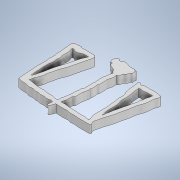
# Autodesk Inventor part: balanta
Saved by Autodesk Inventor 2022.6 (Build 266554000, 554)
## iProperties
Created: 2024-11-29
Part Number: balanta
Material: Generic
Document SubType Name: Modeling
Designer: Dragos Macovei
Density: 1 g/cm^3
Appearance: Default
Author: Dragos Macovei
Autodesk Inventor part; units mm, degrees
ref_plane "YZ Plane" through (0, 0, 0) normal (1, 0, 0) x (0, 1, 0)
ref_plane "XZ Plane" through (0, 0, 0) normal (0, 1, 0) x (-1, 0, 0)
ref_plane "XY Plane" through (0, 0, 0) normal (0, 0, 1) x (1, 0, 0)
sketch "Sketch1" plane through (0, 0, 0) normal (0, 1, 0) x (-1, 0, 0)
  line L0 (0, 0) -> (40, 0)
  line L1 (40, 0) -> (40, 40)
  line L2 (40, 40) -> (0, 40)
  line L3 (0, 40) -> (0, 0)
  line L4 (-121.6723, 119.328) -> (149.4788, 116.0761) construction
  line L5 (149.4788, 116.0761) -> (145.1429, -245.4588) construction
  line L6 (145.1429, -245.4588) -> (-126.0082, -242.2068) construction
  line L7 (-126.0082, -242.2068) -> (-121.6723, 119.328) construction
  spline S0 degree 4 poles (18.132, 10.989) (16.9377, 10.9556) (17.9969, 8.7031) (16.3174, 9.7065) (16.3802, 7.1587) (15.244, 7.8186) (16.3931, 5.6588) (15.388, 6.4386) (15.9001, 5.8958) knots 0 0 0 0 0 0.382596 0.513783 0.647859 0.765558 1 1 1 1 1
  spline S1 degree 4 poles (15.9001, 5.8958) (16.1869, 6.4535) (16.7122, 5.1482) (16.9845, 5.99) (17.8067, 5.5515) (18.1772, 5.8918) (19.1534, 5.4252) (20.1172, 5.2229) (21.245, 4.874) (21.9533, 5.6519) (22.2326, 5.7647) (22.3392, 5.669) knots 0 0 0 0 0 0.217748 0.302019 0.392709 0.499027 0.616777 0.744599 0.858933 1 1 1 1 1
  arc A0 (23.208, 5.1808) -> (23.5743, 7.797) centre (22.364, 6.6327) ccw
  spline S2 degree 4 poles (19.493, 10.8143) (20.5057, 10.7236) (19.2906, 9.4163) (23.7596, 9.3762) (22.5943, 7.6044) (23.2286, 7.7842) (23.5743, 7.797) knots 0 0 0 0 0 0.530729 0.735737 1 1 1 1 1
  line L8 (22.8288, 7.7694) -> (24.3198, 7.8246) construction
  arc A1 (24.1442, 7.7271) -> (23.0111, 7.6852) centre (23.6414, 5.984) ccw construction
  arc A2 (22.3392, 5.669) -> (23.208, 5.1808) centre (23.0369, 5.8934) ccw
  spline S3 degree 2 poles (23.208, 5.1808) (23.1636, 5.1563) (23.1223, 5.1342) knots 0 0 0 1 1 1
  spline S4 degree 2 poles (22.5517, 4.9638) (22.5482, 4.9867) (22.5627, 5.0238) knots 0 0 0 1 1 1
  line L9 (23.1307, 5.1387) -> (23.1138, 5.1297) construction
  arc A3 (23.1155, 5.1306) -> (23.129, 5.1378) centre (20.0172, 10.9465) ccw construction
  line L10 (22.5524, 4.9591) -> (22.551, 4.9684) construction
  arc A4 (22.5513, 4.9675) -> (22.5524, 4.9601) centre (22.6046, 4.972) ccw construction
  line L11 (21.8645, 6.0949) -> (22.814, 5.243) construction
  arc A5 (22.3866, 5.4635) -> (22.1298, 5.6939) centre (22.2168, 5.5326) ccw construction
  spline S5 degree 4 poles (19.493, 10.8143) (19.8087, 12.264) (19.6096, 12.4075) (20.204, 13.9047) (20.1561, 15.6538) (19.9936, 16.1908) (19.8879, 17.7005) (20.2709, 18.1921) (19.9017, 18.9518) (20.0375, 20.0341) (20.0304, 20.6672) (19.9423, 21.5302) (20.6727, 22.1469) (20.1582, 22.7661) (20.6805, 23.2642) (20.4681, 24.3161) (20.6586, 25.3216) (20.5583, 26.2885) (20.9201, 26.8881) (20.8326, 27.3183) (20.9422, 28.0809) (21.3148, 28.8849) (21.1015, 29.5036) (21.0814, 29.9082) (21.4947, 30.0904) knots 0 0 0 0 0 0.129561 0.176077 0.225554 0.2708 0.313451 0.35764 0.398703 0.441175 0.483785 0.522845 0.560251 0.598759 0.640177 0.684668 0.729384 0.770092 0.80779 0.843897 0.880003 0.916311 1 1 1 1 1
  spline S6 degree 4 poles (18.132, 10.989) (18.363, 10.9506) (17.7272, 12.7837) (18.4025, 12.5804) (18.3511, 14.0319) (18.6863, 14.181) (18.3321, 14.9937) (18.4626, 15.8002) (18.4823, 16.2223) (18.2977, 17.3794) (18.6567, 17.5875) (18.6985, 18.0812) (18.4842, 18.7532) (18.4734, 19.1898) (18.5723, 19.738) (18.3245, 20.268) (19.0514, 20.4226) (18.1873, 21.0269) (18.7712, 21.3109) (18.6609, 22.083) (18.8368, 22.432) (19.0187, 23.189) (18.968, 23.8464) (18.9728, 24.1736) (19.0152, 24.8987) (18.8612, 25.4918) (19.2356, 26.2382) (19.613, 26.2439) (19.4622, 26.9642) (19.5256, 27.3102) (19.4707, 27.7706) (19.5764, 28.3088) (19.3232, 28.7552) (20.125, 29.0642) (19.4029, 29.8001) (20.2349, 29.6817) (19.8944, 30.0904) knots 0 0 0 0 0 0.082143 0.112449 0.140884 0.171099 0.200602 0.233945 0.265207 0.293932 0.322849 0.349196 0.376945 0.404826 0.430442 0.456328 0.481282 0.507676 0.535174 0.563931 0.593945 0.622118 0.651214 0.680217 0.709568 0.738223 0.766213 0.792195 0.816766 0.843312 0.868928 0.894585 0.920052 0.943413 1 1 1 1 1
  spline S7 degree 4 poles (19.8944, 30.0904) (19.2465, 30.2807) (18.6456, 29.7635) (17.4707, 30.418) (16.4059, 30.1651) (15.3607, 30.3952) (14.2278, 30.2137) (13.7344, 30.4113) (12.625, 30.5319) (11.3487, 30.4862) (10.0173, 30.2615) (9.7342, 30.9369) (9.0071, 30.5654) knots 0 0 0 0 0 0.206138 0.290024 0.376045 0.458029 0.541696 0.625244 0.709278 0.795062 1 1 1 1 1
  spline S8 degree 4 poles (9.0071, 30.5654) (8.4219, 30.1169) (10.0785, 28.6972) (9.2962, 27.4847) (9.7813, 24.9762) (9.4246, 23.4253) (10.0795, 20.681) (9.7523, 19.9522) (10.5372, 17.9448) (9.9426, 15.9231) (11.0337, 14.8105) (10.9021, 14.263) (11.3029, 13.0531) (11.5369, 11.6262) (11.2807, 11.1554) (11.7405, 9.5379) (11.6911, 9.5623) knots 0 0 0 0 0 0.153003 0.224165 0.299674 0.373236 0.447458 0.52266 0.591018 0.65568 0.715864 0.770166 0.822127 0.879541 1 1 1 1 1
  spline S9 degree 4 poles (11.6911, 9.5623) (11.0397, 8.1763) (10.9108, 10.6325) (9.4517, 8.6495) (8.0933, 9.3323) (5.7453, 9.0917) (4.9328, 9.0991) (3.038, 9.5571) (2.9015, 9.5623) knots 0 0 0 0 0 0.27847 0.406511 0.542996 0.685393 1 1 1 1 1
  spline S10 degree 4 poles (7.0578, 31.4605) (7.633, 30.3741) (7.5017, 31.1396) (6.8335, 26.5484) (5.6939, 24.7894) (5.6129, 22.0557) (4.5273, 19.5602) (4.6969, 16.7593) (3.279, 15.0866) (3.5114, 10.5704) (2.6316, 10.9893) (2.765, 9.5992) (2.9015, 9.5623) knots 0 0 0 0 0 0.183697 0.275142 0.379614 0.480892 0.585044 0.692104 0.78584 0.867689 1 1 1 1 1
  spline S11 degree 4 poles (20.1296, 31.7545) (19.2976, 31.6585) (18.5656, 31.9038) (17.174, 31.8409) (15.5612, 31.5968) (14.6824, 32.1896) (13.5118, 31.7986) (11.963, 32.1354) (9.3916, 32.105) (8.2664, 32.0697) (6.4571, 32.2204) (7.0578, 31.4605) knots 0 0 0 0 0 0.220261 0.305789 0.391276 0.48013 0.577109 0.680805 0.786983 1 1 1 1 1
  spline S12 degree 4 poles (21.7153, 31.6407) (22.1893, 31.3775) (22.5714, 31.4154) (24.0919, 31.9462) (24.6116, 31.2394) (26.9598, 31.7394) (26.9886, 31.0159) (28.6317, 31.5563) (28.859, 30.8759) (30.4367, 31.1461) (31.1954, 31.2232) (32.6471, 30.4288) (33.3628, 31.049) (35.2507, 30.4449) (35.4861, 30.3829) knots 0 0 0 0 0 0.157289 0.231785 0.304485 0.378935 0.451948 0.520541 0.592436 0.662945 0.735378 0.809204 1 1 1 1 1
  spline S13 degree 4 poles (36.916, 9.4382) (37.0506, 9.686) (36.6296, 11.175) (36.8885, 11.4877) (36.4403, 13.6094) (36.5876, 14.6914) (36.1787, 16.1517) (36.1984, 17.1614) (36.4678, 18.6892) (35.9506, 19.1536) (36.2118, 20.6825) (36.0617, 22.0681) (36.2312, 23.5039) (35.8389, 25.2376) (36.002, 27.2433) (35.5623, 29.2226) (35.8015, 30.2555) (35.4861, 30.3829) knots 0 0 0 0 0 0.127862 0.185006 0.244186 0.306313 0.367213 0.423824 0.479586 0.537085 0.59594 0.66131 0.729642 0.800291 0.86926 1 1 1 1 1
  spline S14 degree 2 poles (36.916, 9.4382) (36.8801, 8.8271) (35.8821, 8.4061) knots 0 0 0 1 1 1
  spline S15 degree 4 poles (35.8821, 8.4061) (35.409, 8.1737) (35.7153, 8.8784) (33.7695, 7.8965) (34.3281, 8.5867) (32.9771, 8.62) (32.5996, 8.5899) (30.065, 8.5888) (30.2756, 8.6501) (28.3735, 8.4414) (28.4027, 8.9606) knots 0 0 0 0 0 0.206371 0.290503 0.379024 0.480607 0.596524 0.718915 1 1 1 1 1
  spline S16 degree 4 poles (33.1763, 28.9129) (33.0073, 28.7682) (32.9229, 26.8053) (31.7019, 25.5779) (31.8405, 23.1385) (31.1302, 21.5301) (31.0427, 19.735) (29.9456, 17.8303) (29.6623, 16.1276) (28.9464, 13.2137) (28.4985, 11.2356) (27.7706, 9.1128) (28.4027, 8.9606) knots 0 0 0 0 0 0.179727 0.265075 0.35007 0.437142 0.524636 0.615169 0.70881 0.803069 1 1 1 1 1
  spline S17 degree 4 poles (35.2221, 10.6137) (35.4358, 11.0473) (34.6064, 11.8566) (34.9271, 12.5124) (34.7536, 13.8018) (35.0239, 14.5642) (34.1601, 16.1965) (34.8692, 16.8695) (34.367, 17.8801) (34.4194, 18.9288) (34.6911, 19.8104) (34.6337, 20.4897) (34.6547, 21.6336) (34.659, 22.7266) (34.2941, 24.2065) (34.6774, 25.4188) (34.1471, 26.5279) (34.3422, 26.9533) knots 0 0 0 0 0 0.132208 0.18634 0.245801 0.306639 0.368393 0.431191 0.488916 0.54532 0.602537 0.660509 0.72058 0.784183 0.848811 1 1 1 1 1
  spline S18 degree 4 poles (34.3422, 26.9533) (33.8337, 27.0364) (33.5762, 25.0377) (33.0111, 23.743) (32.6772, 20.8151) (32.1811, 19.2978) (31.2237, 16.2283) (30.7744, 14.3388) (30.3724, 12.2235) (29.7886, 11.2409) knots 0 0 0 0 0 0.234109 0.34792 0.464736 0.583309 0.701819 1 1 1 1 1
  spline S19 degree 4 poles (35.2221, 10.6137) (34.4884, 10.2024) (34.4509, 11.0847) (33.1921, 11.1207) (32.1691, 10.642) (31.1018, 9.955) (30.0184, 10.7431) (28.9526, 9.5202) (29.7886, 11.2409) knots 0 0 0 0 0 0.295683 0.418107 0.545134 0.67151 1 1 1 1 1
  spline S20 degree 4 poles (33.1763, 28.9129) (32.8409, 28.8401) (31.9918, 29.0173) (30.8283, 29.1933) (29.131, 29.5442) (27.8723, 29.5127) (26.6756, 29.3427) (25.1234, 30.1046) (23.3009, 29.3125) (22.4136, 30.294) (21.4947, 30.0904) knots 0 0 0 0 0 0.215092 0.316763 0.420494 0.52389 0.627617 0.731995 1 1 1 1 1
  spline S21 degree 4 poles (7.8201, 26.6686) (7.964, 26.2095) (8.4592, 24.1423) (8.3649, 23.0913) (8.2662, 19.4948) (9.2711, 19.1496) (8.8948, 16.3594) (9.1031, 16.0003) (9.0645, 15.1574) (9.3315, 14.1707) (9.4027, 13.4234) (9.8686, 12.0063) (9.4445, 11.4496) (9.8055, 11.1953) knots 0 0 0 0 0 0.224162 0.319854 0.418281 0.505519 0.580891 0.653027 0.713495 0.779646 0.847839 1 1 1 1 1
  spline S22 degree 4 poles (9.8055, 11.1953) (9.5486, 10.7696) (9.0457, 11.0437) (8.1491, 11.2638) (7.2712, 10.8642) (6.1038, 10.9475) (5.2311, 11.1114) (4.7559, 10.5598) (4.7022, 11.0569) knots 0 0 0 0 0 0.303787 0.439026 0.579761 0.716144 1 1 1 1 1
  spline S23 degree 4 poles (4.7022, 11.0569) (4.7905, 11.3026) (4.3952, 11.7221) (5.4869, 12.8947) (4.8677, 13.9693) (5.6987, 14.7109) (5.2402, 15.8014) (5.7302, 16.6815) (5.8987, 17.18) (5.9649, 17.8897) (6.1325, 18.5804) (6.1814, 19.1042) (6.5021, 19.7026) (6.5603, 20.493) (6.8043, 21.2987) (6.9688, 21.9977) (7.0227, 22.4523) (7.3241, 23.2417) (7.3649, 23.914) (7.4234, 24.8758) (7.8279, 25.4585) (7.6394, 26.1292) (7.8201, 26.6686) knots 0 0 0 0 0 0.103787 0.153755 0.206999 0.258702 0.308098 0.355911 0.400844 0.442694 0.485101 0.528746 0.574005 0.620422 0.665657 0.710458 0.754067 0.79775 0.842362 0.88583 1 1 1 1 1
  spline S24 degree 4 poles (20.1296, 31.7545) (20.505, 31.736) (20.2331, 31.9018) (20.4361, 32.5671) (20.6795, 32.8215) (20.912, 33.3507) (20.848, 33.6973) (21.3624, 33.6331) (21.4563, 33.4649) (21.8725, 33.1843) (21.4198, 32.687) (21.8103, 32.2015) (21.3843, 31.5657) (21.7153, 31.6407) knots 0 0 0 0 0 0.179486 0.26243 0.344573 0.422557 0.497143 0.566953 0.639527 0.716435 0.802627 1 1 1 1 1
  point P0 (17.38, 9.9233)
  point P1 (17.0863, 9.1746)
  point P2 (16.5282, 8.5989)
  point P3 (16.0748, 7.4999)
  point P4 (15.7784, 7.308)
  point P5 (15.8829, 6.3663)
  point P6 (15.7608, 6.192)
  point P7 (16.8598, 5.6364)
  point P8 (17.2239, 5.7338)
  point P9 (17.7121, 5.6811)
  point P10 (18.1293, 5.7305)
  point P11 (18.968, 5.5418)
  point P12 (20.1553, 5.1967)
  point P13 (21.2895, 5.1808)
  point P14 (22.0918, 5.6689)
  point P15 (21.1561, 9.4387)
  point P16 (22.8011, 8.4055)
  point P17 (22.948, 7.8427)
  point P18 (19.7511, 12.4095)
  point P19 (19.8892, 13.1705)
  point P20 (20.1222, 14.4482)
  point P21 (20.1209, 15.5869)
  point P22 (20.0078, 16.3674)
  point P23 (20.0082, 17.6498)
  point P24 (20.1212, 18.2447)
  point P25 (20.01, 18.9506)
  point P26 (20.0121, 19.9899)
  point P27 (20.0144, 20.7388)
  point P28 (20.1295, 21.538)
  point P29 (20.438, 22.2047)
  point P30 (20.3607, 22.7118)
  point P31 (20.495, 23.2185)
  point P32 (20.5502, 24.2023)
  point P33 (20.6051, 25.4238)
  point P34 (20.6854, 26.3786)
  point P35 (20.8439, 26.9076)
  point P36 (20.8696, 27.3297)
  point P37 (20.9742, 28.0422)
  point P38 (21.1632, 28.727)
  point P39 (21.1611, 29.2791)
  point P40 (21.1588, 29.7248)
  point P41 (18.1301, 11.6616)
  point P42 (18.1285, 12.6921)
  point P43 (18.3126, 13.1741)
  point P44 (18.4435, 13.9324)
  point P45 (18.5479, 14.2484)
  point P46 (18.4414, 14.9094)
  point P47 (18.4409, 15.7296)
  point P48 (18.4407, 16.3731)
  point P49 (18.4374, 17.3352)
  point P50 (18.6, 17.6555)
  point P51 (18.6534, 18.0602)
  point P52 (18.5221, 18.7234)
  point P53 (18.4968, 19.2278)
  point P54 (18.4981, 19.7854)
  point P55 (18.5259, 20.2107)
  point P56 (18.739, 20.477)
  point P57 (18.476, 20.9557)
  point P58 (18.6099, 21.3547)
  point P59 (18.7177, 21.9924)
  point P60 (18.8251, 22.4708)
  point P61 (18.9758, 23.215)
  point P62 (18.9772, 23.825)
  point P63 (18.9782, 24.1977)
  point P64 (18.9792, 24.8335)
  point P65 (18.98, 25.5758)
  point P66 (19.3079, 26.1586)
  point P67 (19.5032, 26.371)
  point P68 (19.503, 26.9002)
  point P69 (19.5025, 27.3231)
  point P70 (19.5017, 27.7712)
  point P71 (19.5008, 28.3261)
  point P72 (19.4997, 28.7225)
  point P73 (19.7587, 29.0639)
  point P74 (19.7573, 29.4857)
  point P75 (19.8959, 29.7219)
  point P76 (18.97, 30.0904)
  point P77 (18.1316, 30.0904)
  point P78 (17.2253, 30.2461)
  point P79 (16.4058, 30.2461)
  point P80 (15.3015, 30.3145)
  point P81 (14.2752, 30.2917)
  point P82 (13.6823, 30.3829)
  point P83 (12.7244, 30.4969)
  point P84 (11.6297, 30.4741)
  point P85 (10.5579, 30.4514)
  point P86 (9.8509, 30.6338)
  point P87 (9.0071, 29.7203)
  point P88 (9.5674, 28.3178)
  point P89 (9.5674, 26.9533)
  point P90 (9.6345, 25.1671)
  point P91 (9.6249, 23.2087)
  point P92 (9.9034, 20.8458)
  point P93 (9.961, 19.7912)
  point P94 (10.264, 17.8983)
  point P95 (10.3742, 15.7398)
  point P96 (10.87, 14.7581)
  point P97 (10.9936, 14.1921)
  point P98 (11.2542, 13.096)
  point P99 (11.4229, 12.0152)
  point P100 (11.4305, 11.241)
  point P101 (11.6297, 9.9233)
  point P102 (10.9936, 9.1746)
  point P103 (10.3742, 9.5622)
  point P104 (9.2898, 9.1746)
  point P105 (8.092, 9.1746)
  point P106 (6.4284, 9.1746)
  point P107 (5.1307, 9.1746)
  point P108 (3.5337, 9.4382)
  point P109 (7.4523, 30.6338)
  point P110 (7.3669, 29.9205)
  point P111 (6.5941, 26.7397)
  point P112 (5.8806, 24.5994)
  point P113 (5.4347, 22.2019)
  point P114 (4.7808, 19.5161)
  point P115 (4.3646, 16.9596)
  point P116 (3.5337, 14.2557)
  point P117 (3.1459, 11.2409)
  point P118 (2.8646, 10.6136)
  point P119 (2.792, 9.8675)
  point P120 (18.97, 31.7678)
  point P121 (17.9331, 31.8296)
  point P122 (16.6959, 31.7545)
  point P123 (15.5825, 31.7545)
  point P124 (14.7165, 31.9842)
  point P125 (13.6823, 31.9533)
  point P126 (12.0566, 32.0461)
  point P127 (9.961, 32.108)
  point P128 (8.3451, 32.108)
  point P129 (7.0579, 31.9843)
  point P130 (22.3392, 31.4605)
  point P131 (23.1222, 31.5747)
  point P132 (24.0272, 31.6407)
  point P133 (24.795, 31.4605)
  point P134 (26.7088, 31.4605)
  point P135 (27.3028, 31.2667)
  point P136 (28.4027, 31.3107)
  point P137 (29.0187, 31.0908)
  point P138 (30.3165, 31.1128)
  point P139 (31.2625, 31.0908)
  point P140 (32.1644, 30.8048)
  point P141 (33.0003, 30.7608)
  point P142 (34.4742, 30.6338)
  point P143 (36.894, 10.1925)
  point P144 (36.762, 11.2409)
  point P145 (36.718, 12.0151)
  point P146 (36.542, 13.4482)
  point P147 (36.476, 14.758)
  point P148 (36.256, 16.132)
  point P149 (36.256, 17.3422)
  point P150 (36.3, 18.5738)
  point P151 (36.1241, 19.2328)
  point P152 (36.1241, 20.4791)
  point P153 (36.1241, 21.9906)
  point P154 (36.1241, 23.4574)
  point P155 (35.9481, 25.1671)
  point P156 (35.8821, 26.9533)
  point P157 (35.7281, 28.913)
  point P158 (35.6621, 30.0904)
  point P159 (36.718, 8.9607)
  point P160 (35.4861, 8.4061)
  point P161 (34.8262, 8.4061)
  point P162 (34.1442, 8.2787)
  point P163 (34.0782, 8.4061)
  point P164 (33.4183, 8.5989)
  point P165 (32.4944, 8.5989)
  point P166 (30.8665, 8.5989)
  point P167 (30.1186, 8.5989)
  point P168 (29.0186, 8.5989)
  point P169 (33.0003, 28.3178)
  point P170 (32.4944, 26.5372)
  point P171 (31.9224, 24.9533)
  point P172 (31.6804, 23.2087)
  point P173 (31.2625, 21.5387)
  point P174 (30.8665, 19.7912)
  point P175 (30.1186, 17.8983)
  point P176 (29.6346, 16.132)
  point P177 (29.1287, 13.9374)
  point P178 (28.5567, 11.6628)
  point P179 (28.1168, 9.5622)
  point P180 (35.0901, 11.3804)
  point P181 (34.8262, 12.1504)
  point P182 (34.8262, 12.8323)
  point P183 (34.8262, 13.6682)
  point P184 (34.8262, 14.5922)
  point P185 (34.4742, 16.132)
  point P186 (34.6282, 16.9596)
  point P187 (34.4742, 17.8983)
  point P188 (34.4742, 18.9605)
  point P189 (34.6282, 19.7912)
  point P190 (34.6502, 20.4791)
  point P191 (34.6502, 21.5387)
  point P192 (34.6062, 22.7063)
  point P193 (34.4742, 23.8197)
  point P194 (34.4742, 24.9533)
  point P195 (34.3422, 26.1509)
  point P196 (33.9022, 26.5371)
  point P197 (33.4183, 24.8266)
  point P198 (33.0003, 23.0614)
  point P199 (32.6263, 20.9565)
  dimension "d0" = 40
  dimension "d1" = 40
  constraints: 16 end point, 10 point on circle, 8 midpoint, 6 centre point, 2 parallel, 1 horizontal, 1 perpendicular, 334 other
  measures "d0" distance of L2.end L1.end
  measures "d1" distance of L1.end L0.end
extrude "Extrusion1" add sketch "Sketch1" along normal blind 3 contours S6 S7 S8 S9 S10 S11 S24 S12 S13 S14 S15 S16 S20 S5 S2 A0 A2 S1 S0
body "Solid1"
